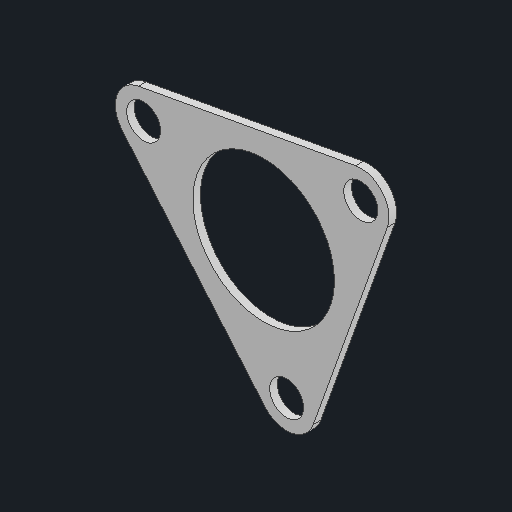
# Autodesk Inventor part: Carer
Saved by Autodesk Inventor 2027.1 (Build 311270010, 270A)
## iProperties
Created: 2026-11-11
Part Number: Carer
Material: 一般
Document SubType Name: Modeling
Designer: takuya
Density: 1 g/cm^3
Appearance: 既定
Author: takuya
Autodesk Inventor part; units mm, degrees
ref_plane "YZ Plane" through (0, 0, 0) normal (1, 0, 0) x (0, 1, 0)
ref_plane "XZ Plane" through (0, 0, 0) normal (0, 1, 0) x (-1, 0, 0)
ref_plane "XY Plane" through (0, 0, 0) normal (0, 0, 1) x (1, 0, 0)
sketch "スケッチ1" plane through (0, 0, 0) normal (0, 0, 1) x (1, 0, 0)
  circle A0 centre (-26.1969, -73.4079) radius 6
  circle A1 centre (-76.6716, -14.0167) radius 6
  circle A2 centre (0, 0) radius 6
  circle A3 centre (0, 0) radius 10
  circle A4 centre (-76.6716, -14.0167) radius 10
  circle A5 centre (-26.1969, -73.4079) radius 10
  circle A6 centre (-34.2895, -29.1415) radius 3
  circle A7 centre (-34.2895, -29.1415) radius 35
  line L0 (-84.2915, -20.4926) -> (-33.8168, -79.8838)
  line L1 (-16.7787, -76.769) -> (9.4182, -3.3611)
  line L2 (-78.4699, -4.1798) -> (-1.7983, 9.837)
  circle A8 centre (-34.2895, -29.1415) radius 25
  dimension "d0" = 20
  dimension "d1" = 20
  dimension "d2" = 20
  dimension "d3" = 50
  constraints: 9 centre point, 6 end point, 6 point on circle, 5 coincident
  measures "d0" diameter of A3
  measures "d1" diameter of A5
  measures "d2" diameter of A4
  measures "d3" diameter of A8
extrude "押し出し1" add sketch "スケッチ1" along normal blind 2.7 contours A3 | A3 A7 L2 | L1 A7 A3 | A7 L1 L0 L2 | A7 A4 L2 | L1 A5 A7 | A7 L0 A4 | A4 | A5 | A5 L0 A7
equation "\"d1\" = d0"
equation "\"d2\" = d1"
